Autodesk Fusion 360 part; units mm, degrees
(part 17 of 28)
  line L322 (99.1222, 11.5551) -> (98.9836, 11.4165)
  line L323 (98.9836, 11.4165) -> (98.8249, 11.3012)
  line L324 (98.8249, 11.3012) -> (98.6501, 11.2121)
  line L325 (98.6501, 11.2121) -> (98.4635, 11.1515)
  line L326 (98.4635, 11.1515) -> (98.2698, 11.1208)
  line L327 (98.2698, 11.1208) -> (98.1717, 11.117)
  line L328 (98.1717, 11.117) -> (97.6717, 11.117)
  line L329 (97.6717, 11.117) -> (97.5737, 11.1208)
  line L330 (97.5737, 11.1208) -> (97.3799, 11.1515)
  line L331 (97.3799, 11.1515) -> (97.1934, 11.2121)
  line L332 (97.1934, 11.2121) -> (97.0186, 11.3012)
  line L333 (97.0186, 11.3012) -> (96.8599, 11.4165)
  line L334 (96.8599, 11.4165) -> (96.7212, 11.5551)
  line L335 (96.7212, 11.5551) -> (96.6059, 11.7138)
  line L336 (96.6059, 11.7138) -> (96.5169, 11.8886)
  line L337 (96.5169, 11.8886) -> (96.4563, 12.0751)
  line L338 (96.4563, 12.0751) -> (96.4256, 12.2689)
  line L339 (96.4256, 12.2689) -> (96.4256, 12.465)
  line L340 (96.4256, 12.465) -> (96.4563, 12.6588)
  line L341 (96.4563, 12.6588) -> (96.5169, 12.8453)
  line L342 (96.5169, 12.8453) -> (96.6059, 13.0201)
  line L343 (96.6059, 13.0201) -> (96.7212, 13.1788)
  line L344 (96.7212, 13.1788) -> (96.8599, 13.3175)
  line L345 (96.8599, 13.3175) -> (97.0186, 13.4328)
  line L346 (97.0186, 13.4328) -> (97.1934, 13.5218)
  line L347 (97.1934, 13.5218) -> (97.3799, 13.5824)
  line L348 (97.3799, 13.5824) -> (97.5737, 13.6131)
  line L349 (97.5737, 13.6131) -> (97.6717, 13.617)
  line L350 (97.6717, 13.617) -> (98.1717, 13.617)
  line L351 (98.1717, 13.617) -> (98.2698, 13.6131)
  line L352 (43.7883, 16.6386) -> (43.9806, 16.6003)
  line L353 (43.9806, 16.6003) -> (44.1617, 16.5253)
  line L354 (44.1617, 16.5253) -> (44.3247, 16.4164)
  line L355 (44.3247, 16.4164) -> (44.4633, 16.2778)
  line L356 (44.4633, 16.2778) -> (44.5722, 16.1148)
  line L357 (44.5722, 16.1148) -> (44.6472, 15.9337)
  line L358 (44.6472, 15.9337) -> (44.6855, 15.7414)
  line L359 (44.6855, 15.7414) -> (44.6855, 15.5454)
  line L360 (44.6855, 15.5454) -> (44.6472, 15.3531)
  line L361 (44.6472, 15.3531) -> (44.5722, 15.172)
  line L362 (44.5722, 15.172) -> (44.4633, 15.009)
  line L363 (44.4633, 15.009) -> (44.3247, 14.8704)
  line L364 (44.3247, 14.8704) -> (44.1617, 14.7615)
  line L365 (44.1617, 14.7615) -> (43.9806, 14.6865)
  line L366 (43.9806, 14.6865) -> (43.7883, 14.6482)
  line L367 (43.7883, 14.6482) -> (43.6903, 14.6434)
  line L368 (43.6903, 14.6434) -> (42.4903, 14.6434)
  line L369 (42.4903, 14.6434) -> (42.3923, 14.6482)
  line L370 (42.3923, 14.6482) -> (42.2, 14.6865)
  line L371 (42.2, 14.6865) -> (42.0189, 14.7615)
  line L372 (42.0189, 14.7615) -> (41.8559, 14.8704)
  line L373 (41.8559, 14.8704) -> (41.7173, 15.009)
  line L374 (41.7173, 15.009) -> (41.6084, 15.172)
  line L375 (41.6084, 15.172) -> (41.5333, 15.3531)
  line L376 (41.5333, 15.3531) -> (41.4951, 15.5454)
  line L377 (41.4951, 15.5454) -> (41.4951, 15.7414)
  line L378 (41.4951, 15.7414) -> (41.5333, 15.9337)
  line L379 (41.5333, 15.9337) -> (41.6084, 16.1148)
  line L380 (41.6084, 16.1148) -> (41.7173, 16.2778)
  line L381 (41.7173, 16.2778) -> (41.8559, 16.4164)
  line L382 (41.8559, 16.4164) -> (42.0189, 16.5253)
  line L383 (42.0189, 16.5253) -> (42.2, 16.6003)
  line L384 (42.2, 16.6003) -> (42.3923, 16.6386)
  line L385 (42.3923, 16.6386) -> (42.4903, 16.6434)
  line L386 (42.4903, 16.6434) -> (43.6903, 16.6434)
  line L387 (43.6903, 16.6434) -> (43.7883, 16.6386)
  line L388 (104.7483, 16.6386) -> (104.9406, 16.6003)
  line L389 (104.9406, 16.6003) -> (105.1217, 16.5253)
  line L390 (105.1217, 16.5253) -> (105.2847, 16.4164)
  line L391 (105.2847, 16.4164) -> (105.4233, 16.2778)
  line L392 (105.4233, 16.2778) -> (105.5322, 16.1148)
  line L393 (105.5322, 16.1148) -> (105.6072, 15.9337)
  line L394 (105.6072, 15.9337) -> (105.6455, 15.7414)
  line L395 (105.6455, 15.7414) -> (105.6455, 15.5454)
  line L396 (105.6455, 15.5454) -> (105.6072, 15.3531)
  line L397 (105.6072, 15.3531) -> (105.5322, 15.172)
  line L398 (105.5322, 15.172) -> (105.4233, 15.009)
  line L399 (105.4233, 15.009) -> (105.2847, 14.8704)
  line L400 (105.2847, 14.8704) -> (105.1217, 14.7615)
  line L401 (105.1217, 14.7615) -> (104.9406, 14.6865)
  line L402 (104.9406, 14.6865) -> (104.7483, 14.6482)
  line L403 (104.7483, 14.6482) -> (104.6503, 14.6434)
  line L404 (104.6503, 14.6434) -> (103.4503, 14.6434)
  line L405 (103.4503, 14.6434) -> (103.3523, 14.6482)
  line L406 (103.3523, 14.6482) -> (103.16, 14.6865)
  line L407 (103.16, 14.6865) -> (102.9789, 14.7615)
  line L408 (102.9789, 14.7615) -> (102.8159, 14.8704)
  line L409 (102.8159, 14.8704) -> (102.6773, 15.009)
  line L410 (102.6773, 15.009) -> (102.5684, 15.172)
  line L411 (102.5684, 15.172) -> (102.4933, 15.3531)
  line L412 (102.4933, 15.3531) -> (102.4551, 15.5454)
  line L413 (102.4551, 15.5454) -> (102.4551, 15.7414)
  line L414 (102.4551, 15.7414) -> (102.4933, 15.9337)
  line L415 (102.4933, 15.9337) -> (102.5684, 16.1148)
  line L416 (102.5684, 16.1148) -> (102.6773, 16.2778)
  line L417 (102.6773, 16.2778) -> (102.8159, 16.4164)
  line L418 (102.8159, 16.4164) -> (102.9789, 16.5253)
  line L419 (102.9789, 16.5253) -> (103.16, 16.6003)
  line L420 (103.16, 16.6003) -> (103.3523, 16.6386)
  line L421 (103.3523, 16.6386) -> (103.4503, 16.6434)
  line L422 (103.4503, 16.6434) -> (104.6503, 16.6434)
  line L423 (104.6503, 16.6434) -> (104.7483, 16.6386)
  line L424 (21.9611, 19.0012) -> (22.151, 18.9712)
  line L425 (22.151, 18.9712) -> (22.3338, 18.9118)
  line L426 (22.3338, 18.9118) -> (22.5051, 18.8245)
  line L427 (22.5051, 18.8245) -> (22.6606, 18.7115)
  line L428 (22.6606, 18.7115) -> (22.7965, 18.5756)
  line L429 (22.7965, 18.5756) -> (22.9095, 18.4201)
  line L430 (22.9095, 18.4201) -> (22.9968, 18.2488)
  line L431 (22.9968, 18.2488) -> (23.0562, 18.066)
  line L432 (23.0562, 18.066) -> (23.0862, 17.8761)
  line L433 (23.0862, 17.8761) -> (23.0862, 17.6839)
  line L434 (23.0862, 17.6839) -> (23.0562, 17.494)
  line L435 (23.0562, 17.494) -> (22.9968, 17.3112)
  line L436 (22.9968, 17.3112) -> (22.9095, 17.1399)
  line L437 (22.9095, 17.1399) -> (22.7965, 16.9844)
  line L438 (22.7965, 16.9844) -> (22.6606, 16.8485)
  line L439 (22.6606, 16.8485) -> (22.5051, 16.7355)
  line L440 (22.5051, 16.7355) -> (22.3338, 16.6482)
  line L441 (22.3338, 16.6482) -> (22.151, 16.5888)
  line L442 (22.151, 16.5888) -> (21.9611, 16.5588)
  line L443 (21.9611, 16.5588) -> (21.865, 16.555)
  line L444 (21.865, 16.555) -> (21.315, 16.555)
  line L445 (21.315, 16.555) -> (21.2189, 16.5588)
  line L446 (21.2189, 16.5588) -> (21.029, 16.5888)
  line L447 (21.029, 16.5888) -> (20.8462, 16.6482)
  line L448 (20.8462, 16.6482) -> (20.6749, 16.7355)
  line L449 (20.6749, 16.7355) -> (20.5194, 16.8485)
  line L450 (20.5194, 16.8485) -> (20.3835, 16.9844)
  line L451 (20.3835, 16.9844) -> (20.2705, 17.1399)
  line L452 (20.2705, 17.1399) -> (20.1832, 17.3112)
  line L453 (20.1832, 17.3112) -> (20.1238, 17.494)
  line L454 (20.1238, 17.494) -> (20.0938, 17.6839)
  line L455 (20.0938, 17.6839) -> (20.0938, 17.8761)
  line L456 (20.0938, 17.8761) -> (20.1238, 18.066)
  line L457 (20.1238, 18.066) -> (20.1832, 18.2488)
  line L458 (20.1832, 18.2488) -> (20.2705, 18.4201)
  line L459 (20.2705, 18.4201) -> (20.3835, 18.5756)
  line L460 (20.3835, 18.5756) -> (20.5194, 18.7115)
  line L461 (20.5194, 18.7115) -> (20.6749, 18.8245)
  line L462 (20.6749, 18.8245) -> (20.8462, 18.9118)
  line L463 (20.8462, 18.9118) -> (21.029, 18.9712)
  line L464 (21.029, 18.9712) -> (21.2189, 19.0012)
  line L465 (21.2189, 19.0012) -> (21.315, 19.005)
  line L466 (21.315, 19.005) -> (21.865, 19.005)
  line L467 (21.865, 19.005) -> (21.9611, 19.0012)
  line L468 (82.9211, 19.0012) -> (83.111, 18.9712)
  line L469 (83.111, 18.9712) -> (83.2938, 18.9118)
  line L470 (83.2938, 18.9118) -> (83.4651, 18.8245)
  line L471 (83.4651, 18.8245) -> (83.6206, 18.7115)
  line L472 (83.6206, 18.7115) -> (83.7565, 18.5756)
  line L473 (83.7565, 18.5756) -> (83.8695, 18.4201)
  line L474 (83.8695, 18.4201) -> (83.9568, 18.2488)
  line L475 (83.9568, 18.2488) -> (84.0162, 18.066)
  line L476 (84.0162, 18.066) -> (84.0462, 17.8761)
  line L477 (84.0462, 17.8761) -> (84.0462, 17.6839)
  line L478 (84.0462, 17.6839) -> (84.0162, 17.494)
  line L479 (84.0162, 17.494) -> (83.9568, 17.3112)
  line L480 (83.9568, 17.3112) -> (83.8695, 17.1399)
  line L481 (83.8695, 17.1399) -> (83.7565, 16.9844)
  line L482 (83.7565, 16.9844) -> (83.6206, 16.8485)
  line L483 (83.6206, 16.8485) -> (83.4651, 16.7355)
  line L484 (83.4651, 16.7355) -> (83.2938, 16.6482)
  line L485 (83.2938, 16.6482) -> (83.111, 16.5888)
  line L486 (83.111, 16.5888) -> (82.9211, 16.5588)
  line L487 (82.9211, 16.5588) -> (82.825, 16.555)
  line L488 (82.825, 16.555) -> (82.275, 16.555)
  line L489 (82.275, 16.555) -> (82.1789, 16.5588)
  line L490 (82.1789, 16.5588) -> (81.989, 16.5888)
  line L491 (81.989, 16.5888) -> (81.8062, 16.6482)
  line L492 (81.8062, 16.6482) -> (81.6349, 16.7355)
  line L493 (81.6349, 16.7355) -> (81.4794, 16.8485)
  line L494 (81.4794, 16.8485) -> (81.3435, 16.9844)
  line L495 (81.3435, 16.9844) -> (81.2305, 17.1399)
  line L496 (81.2305, 17.1399) -> (81.1432, 17.3112)
  line L497 (81.1432, 17.3112) -> (81.0838, 17.494)
  line L498 (81.0838, 17.494) -> (81.0538, 17.6839)
  line L499 (81.0538, 17.6839) -> (81.0538, 17.8761)
  line L500 (81.0538, 17.8761) -> (81.0838, 18.066)
  line L501 (81.0838, 18.066) -> (81.1432, 18.2488)
  line L502 (81.1432, 18.2488) -> (81.2305, 18.4201)
  line L503 (81.2305, 18.4201) -> (81.3435, 18.5756)
  line L504 (81.3435, 18.5756) -> (81.4794, 18.7115)
  line L505 (81.4794, 18.7115) -> (81.6349, 18.8245)
  line L506 (81.6349, 18.8245) -> (81.8062, 18.9118)
  line L507 (81.8062, 18.9118) -> (81.989, 18.9712)
  line L508 (81.989, 18.9712) -> (82.1789, 19.0012)
  line L509 (82.1789, 19.0012) -> (82.275, 19.005)
  line L510 (82.275, 19.005) -> (82.825, 19.005)
  line L511 (82.825, 19.005) -> (82.9211, 19.0012)
  line L512 (43.7883, 19.3686) -> (43.9806, 19.3303)
  line L513 (43.9806, 19.3303) -> (44.1617, 19.2553)
  line L514 (44.1617, 19.2553) -> (44.3247, 19.1464)
  line L515 (44.3247, 19.1464) -> (44.4633, 19.0078)
  line L516 (44.4633, 19.0078) -> (44.5722, 18.8448)
  line L517 (44.5722, 18.8448) -> (44.6472, 18.6637)
  line L518 (44.6472, 18.6637) -> (44.6855, 18.4714)
  line L519 (44.6855, 18.4714) -> (44.6855, 18.2754)
  line L520 (44.6855, 18.2754) -> (44.6472, 18.0831)
  line L521 (44.6472, 18.0831) -> (44.5722, 17.902)
  line L522 (44.5722, 17.902) -> (44.4633, 17.739)
  line L523 (44.4633, 17.739) -> (44.3247, 17.6004)
  line L524 (44.3247, 17.6004) -> (44.1617, 17.4915)
  line L525 (44.1617, 17.4915) -> (43.9806, 17.4165)
  line L526 (43.9806, 17.4165) -> (43.7883, 17.3782)
  line L527 (43.7883, 17.3782) -> (43.6903, 17.3734)
  line L528 (43.6903, 17.3734) -> (42.4903, 17.3734)
  line L529 (42.4903, 17.3734) -> (42.3923, 17.3782)
  line L530 (42.3923, 17.3782) -> (42.2, 17.4165)
  line L531 (42.2, 17.4165) -> (42.0189, 17.4915)
  line L532 (42.0189, 17.4915) -> (41.8559, 17.6004)
  line L533 (41.8559, 17.6004) -> (41.7173, 17.739)
  line L534 (41.7173, 17.739) -> (41.6084, 17.902)
  line L535 (41.6084, 17.902) -> (41.5333, 18.0831)
  line L536 (41.5333, 18.0831) -> (41.4951, 18.2754)
  line L537 (41.4951, 18.2754) -> (41.4951, 18.4714)
  line L538 (41.4951, 18.4714) -> (41.5333, 18.6637)
  line L539 (41.5333, 18.6637) -> (41.6084, 18.8448)
  line L540 (41.6084, 18.8448) -> (41.7173, 19.0078)
  line L541 (41.7173, 19.0078) -> (41.8559, 19.1464)
  line L542 (41.8559, 19.1464) -> (42.0189, 19.2553)
  line L543 (42.0189, 19.2553) -> (42.2, 19.3303)
  line L544 (42.2, 19.3303) -> (42.3923, 19.3686)
  line L545 (42.3923, 19.3686) -> (42.4903, 19.3734)
  line L546 (42.4903, 19.3734) -> (43.6903, 19.3734)
  line L547 (43.6903, 19.3734) -> (43.7883, 19.3686)
  line L548 (104.7483, 19.3686) -> (104.9406, 19.3303)
  line L549 (104.9406, 19.3303) -> (105.1217, 19.2553)
  line L550 (105.1217, 19.2553) -> (105.2847, 19.1464)
  line L551 (105.2847, 19.1464) -> (105.4233, 19.0078)
  line L552 (105.4233, 19.0078) -> (105.5322, 18.8448)
  line L553 (105.5322, 18.8448) -> (105.6072, 18.6637)
  line L554 (105.6072, 18.6637) -> (105.6455, 18.4714)
  line L555 (105.6455, 18.4714) -> (105.6455, 18.2754)
  line L556 (105.6455, 18.2754) -> (105.6072, 18.0831)
  line L557 (105.6072, 18.0831) -> (105.5322, 17.902)
  line L558 (105.5322, 17.902) -> (105.4233, 17.739)
  line L559 (105.4233, 17.739) -> (105.2847, 17.6004)
  line L560 (105.2847, 17.6004) -> (105.1217, 17.4915)
  line L561 (105.1217, 17.4915) -> (104.9406, 17.4165)
  line L562 (104.9406, 17.4165) -> (104.7483, 17.3782)
  line L563 (104.7483, 17.3782) -> (104.6503, 17.3734)
  line L564 (104.6503, 17.3734) -> (103.4503, 17.3734)
  line L565 (103.4503, 17.3734) -> (103.3523, 17.3782)
  line L566 (103.3523, 17.3782) -> (103.16, 17.4165)
  line L567 (103.16, 17.4165) -> (102.9789, 17.4915)
  line L568 (102.9789, 17.4915) -> (102.8159, 17.6004)
  line L569 (102.8159, 17.6004) -> (102.6773, 17.739)
  line L570 (102.6773, 17.739) -> (102.5684, 17.902)
  line L571 (102.5684, 17.902) -> (102.4933, 18.0831)
  line L572 (102.4933, 18.0831) -> (102.4551, 18.2754)
  line L573 (102.4551, 18.2754) -> (102.4551, 18.4714)
  line L574 (102.4551, 18.4714) -> (102.4933, 18.6637)
  line L575 (102.4933, 18.6637) -> (102.5684, 18.8448)
  line L576 (102.5684, 18.8448) -> (102.6773, 19.0078)
  line L577 (102.6773, 19.0078) -> (102.8159, 19.1464)
  line L578 (102.8159, 19.1464) -> (102.9789, 19.2553)
  line L579 (102.9789, 19.2553) -> (103.16, 19.3303)
  line L580 (103.16, 19.3303) -> (103.3523, 19.3686)
  line L581 (103.3523, 19.3686) -> (103.4503, 19.3734)
  line L582 (103.4503, 19.3734) -> (104.6503, 19.3734)
  line L583 (104.6503, 19.3734) -> (104.7483, 19.3686)
  line L584 (22.8164, 21.4891) -> (22.9296, 21.4337)
  line L585 (22.9296, 21.4337) -> (23.0187, 21.3446)
  line L586 (23.0187, 21.3446) -> (23.0741, 21.2314)
  line L587 (23.0741, 21.2314) -> (23.09, 21.1222)
  line L588 (23.09, 21.1222) -> (23.09, 19.4378)
  line L589 (23.09, 19.4378) -> (23.0741, 19.3286)
  line L590 (23.0741, 19.3286) -> (23.0187, 19.2154)
  line L591 (23.0187, 19.2154) -> (22.9296, 19.1263)
  line L592 (22.9296, 19.1263) -> (22.8164, 19.0709)
  line L593 (22.8164, 19.0709) -> (22.7072, 19.055)
  line L594 (22.7072, 19.055) -> (20.4728, 19.055)
  line L595 (20.4728, 19.055) -> (20.3636, 19.0709)
  line L596 (20.3636, 19.0709) -> (20.2504, 19.1263)
  line L597 (20.2504, 19.1263) -> (20.1613, 19.2154)
  line L598 (20.1613, 19.2154) -> (20.1059, 19.3286)
  line L599 (20.1059, 19.3286) -> (20.09, 19.4378)
  line L600 (20.09, 19.4378) -> (20.09, 21.1222)
  line L601 (20.09, 21.1222) -> (20.1059, 21.2314)
  line L602 (20.1059, 21.2314) -> (20.1613, 21.3446)
  line L603 (20.1613, 21.3446) -> (20.2504, 21.4337)
  line L604 (20.2504, 21.4337) -> (20.3636, 21.4891)
  line L605 (20.3636, 21.4891) -> (20.4728, 21.505)
  line L606 (20.4728, 21.505) -> (22.7072, 21.505)
  line L607 (22.7072, 21.505) -> (22.8164, 21.4891)
  line L608 (83.7764, 21.4891) -> (83.8896, 21.4337)
  line L609 (83.8896, 21.4337) -> (83.9787, 21.3446)
  line L610 (83.9787, 21.3446) -> (84.0341, 21.2314)
  line L611 (84.0341, 21.2314) -> (84.05, 21.1222)
  line L612 (84.05, 21.1222) -> (84.05, 19.4378)
  line L613 (84.05, 19.4378) -> (84.0341, 19.3286)
  line L614 (84.0341, 19.3286) -> (83.9787, 19.2154)
  line L615 (83.9787, 19.2154) -> (83.8896, 19.1263)
  line L616 (83.8896, 19.1263) -> (83.7764, 19.0709)
  line L617 (83.7764, 19.0709) -> (83.6672, 19.055)
  line L618 (83.6672, 19.055) -> (81.4328, 19.055)
  line L619 (81.4328, 19.055) -> (81.3236, 19.0709)
  line L620 (81.3236, 19.0709) -> (81.2104, 19.1263)
  line L621 (81.2104, 19.1263) -> (81.1213, 19.2154)
  line L622 (81.1213, 19.2154) -> (81.0659, 19.3286)
  line L623 (81.0659, 19.3286) -> (81.05, 19.4378)
  line L624 (81.05, 19.4378) -> (81.05, 21.1222)
  line L625 (81.05, 21.1222) -> (81.0659, 21.2314)
  line L626 (81.0659, 21.2314) -> (81.1213, 21.3446)
  line L627 (81.1213, 21.3446) -> (81.2104, 21.4337)
  line L628 (81.2104, 21.4337) -> (81.3236, 21.4891)
  line L629 (81.3236, 21.4891) -> (81.4328, 21.505)
  line L630 (81.4328, 21.505) -> (83.6672, 21.505)
  line L631 (83.6672, 21.505) -> (83.7764, 21.4891)
  line L632 (32.7136, 22.7426) -> (32.9001, 22.682)
  line L633 (32.9001, 22.682) -> (33.0749, 22.5929)
  line L634 (33.0749, 22.5929) -> (33.2336, 22.4776)
  line L635 (33.2336, 22.4776) -> (33.3723, 22.3389)
  line L636 (33.3723, 22.3389) -> (33.4876, 22.1802)
  line L637 (33.4876, 22.1802) -> (33.5766, 22.0055)
  line L638 (33.5766, 22.0055) -> (33.6372, 21.8189)
  line L639 (33.6372, 21.8189) -> (33.6679, 21.6252)
  line L640 (33.6679, 21.6252) -> (33.6718, 21.5271)
  line L641 (33.6718, 21.5271) -> (33.6718, 21.0271)
  line L642 (33.6718, 21.0271) -> (33.6679, 20.929)
  line L643 (33.6679, 20.929) -> (33.6372, 20.7353)
  line L644 (33.6372, 20.7353) -> (33.5766, 20.5488)
  line L645 (33.5766, 20.5488) -> (33.4876, 20.374)
  line L646 (33.4876, 20.374) -> (33.3723, 20.2153)
  line L647 (33.3723, 20.2153) -> (33.2336, 20.0766)
  line L648 (33.2336, 20.0766) -> (33.0749, 19.9613)
  line L649 (33.0749, 19.9613) -> (32.9001, 19.8723)
  line L650 (32.9001, 19.8723) -> (32.7136, 19.8117)
  line L651 (32.7136, 19.8117) -> (32.5198, 19.781)
  line L652 (32.5198, 19.781) -> (32.3237, 19.781)
  line L653 (32.3237, 19.781) -> (32.13, 19.8117)
  line L654 (32.13, 19.8117) -> (31.9434, 19.8723)
  line L655 (31.9434, 19.8723) -> (31.7686, 19.9613)
  line L656 (31.7686, 19.9613) -> (31.61, 20.0766)
  line L657 (31.61, 20.0766) -> (31.4713, 20.2153)
  line L658 (31.4713, 20.2153) -> (31.356, 20.374)
  line L659 (31.356, 20.374) -> (31.2669, 20.5488)
  line L660 (31.2669, 20.5488) -> (31.2063, 20.7353)
  line L661 (31.2063, 20.7353) -> (31.1756, 20.929)
  line L662 (31.1756, 20.929) -> (31.1718, 21.0271)
  line L663 (31.1718, 21.0271) -> (31.1718, 21.5271)
  line L664 (31.1718, 21.5271) -> (31.1756, 21.6252)
  line L665 (31.1756, 21.6252) -> (31.2063, 21.8189)
  line L666 (31.2063, 21.8189) -> (31.2669, 22.0055)
  line L667 (31.2669, 22.0055) -> (31.356, 22.1802)
  line L668 (31.356, 22.1802) -> (31.4713, 22.3389)
  line L669 (31.4713, 22.3389) -> (31.61, 22.4776)
  line L670 (31.61, 22.4776) -> (31.7686, 22.5929)
  line L671 (31.7686, 22.5929) -> (31.9434, 22.682)
  line L672 (31.9434, 22.682) -> (32.13, 22.7426)
  line L673 (32.13, 22.7426) -> (32.3237, 22.7733)
  line L674 (32.3237, 22.7733) -> (32.5198, 22.7733)
  line L675 (32.5198, 22.7733) -> (32.7136, 22.7426)
  line L676 (93.6736, 22.7426) -> (93.8601, 22.682)
  line L677 (93.8601, 22.682) -> (94.0349, 22.5929)
  line L678 (94.0349, 22.5929) -> (94.1936, 22.4776)
  line L679 (94.1936, 22.4776) -> (94.3323, 22.3389)
  line L680 (94.3323, 22.3389) -> (94.4476, 22.1802)
  line L681 (94.4476, 22.1802) -> (94.5366, 22.0055)
  line L682 (94.5366, 22.0055) -> (94.5972, 21.8189)
  line L683 (94.5972, 21.8189) -> (94.6279, 21.6252)
  line L684 (94.6279, 21.6252) -> (94.6318, 21.5271)
  line L685 (94.6318, 21.5271) -> (94.6318, 21.0271)
  line L686 (94.6318, 21.0271) -> (94.6279, 20.929)
  line L687 (94.6279, 20.929) -> (94.5972, 20.7353)
  line L688 (94.5972, 20.7353) -> (94.5366, 20.5488)
  line L689 (94.5366, 20.5488) -> (94.4476, 20.374)
  line L690 (94.4476, 20.374) -> (94.3323, 20.2153)
  line L691 (94.3323, 20.2153) -> (94.1936, 20.0766)
  line L692 (94.1936, 20.0766) -> (94.0349, 19.9613)
  line L693 (94.0349, 19.9613) -> (93.8601, 19.8723)
  line L694 (93.8601, 19.8723) -> (93.6736, 19.8117)
  line L695 (93.6736, 19.8117) -> (93.4798, 19.781)
  line L696 (93.4798, 19.781) -> (93.2837, 19.781)
  line L697 (93.2837, 19.781) -> (93.09, 19.8117)
  line L698 (93.09, 19.8117) -> (92.9034, 19.8723)
  line L699 (92.9034, 19.8723) -> (92.7286, 19.9613)
  line L700 (92.7286, 19.9613) -> (92.57, 20.0766)
  line L701 (92.57, 20.0766) -> (92.4313, 20.2153)
  line L702 (92.4313, 20.2153) -> (92.316, 20.374)
  line L703 (92.316, 20.374) -> (92.2269, 20.5488)
  line L704 (92.2269, 20.5488) -> (92.1663, 20.7353)
  line L705 (92.1663, 20.7353) -> (92.1356, 20.929)
  line L706 (92.1356, 20.929) -> (92.1318, 21.0271)
  line L707 (92.1318, 21.0271) -> (92.1318, 21.5271)
  line L708 (92.1318, 21.5271) -> (92.1356, 21.6252)
  line L709 (92.1356, 21.6252) -> (92.1663, 21.8189)
  line L710 (92.1663, 21.8189) -> (92.2269, 22.0055)
  line L711 (92.2269, 22.0055) -> (92.316, 22.1802)
  line L712 (92.316, 22.1802) -> (92.4313, 22.3389)
  line L713 (92.4313, 22.3389) -> (92.57, 22.4776)
  line L714 (92.57, 22.4776) -> (92.7286, 22.5929)
  line L715 (92.7286, 22.5929) -> (92.9034, 22.682)
  line L716 (92.9034, 22.682) -> (93.09, 22.7426)
  line L717 (93.09, 22.7426) -> (93.2837, 22.7733)
  line L718 (93.2837, 22.7733) -> (93.4798, 22.7733)
  line L719 (93.4798, 22.7733) -> (93.6736, 22.7426)
  line L720 (44.6903, 20.1434) -> (41.4903, 20.1434)
  line L721 (41.4903, 20.1434) -> (41.4903, 22.1434)
  line L722 (41.4903, 22.1434) -> (44.6903, 22.1434)
  line L723 (44.6903, 22.1434) -> (44.6903, 20.1434)
  line L724 (105.6503, 20.1434) -> (102.4503, 20.1434)
  line L725 (102.4503, 20.1434) -> (102.4503, 22.1434)
  line L726 (102.4503, 22.1434) -> (105.6503, 22.1434)
  line L727 (105.6503, 22.1434) -> (105.6503, 20.1434)
  line L728 (60.3233, 20.3326) -> (57.3233, 20.3326)
  line L729 (57.3233, 20.3326) -> (57.3233, 22.7826)
  line L730 (57.3233, 22.7826) -> (60.3233, 22.7826)
  line L731 (60.3233, 22.7826) -> (60.3233, 20.3326)
  line L732 (121.2833, 20.3326) -> (118.2833, 20.3326)
  line L733 (118.2833, 20.3326) -> (118.2833, 22.7826)
  line L734 (118.2833, 22.7826) -> (121.2833, 22.7826)
  line L735 (121.2833, 22.7826) -> (121.2833, 20.3326)
  line L736 (50.1338, 24.7863) -> (50.3204, 24.7257)
  line L737 (50.3204, 24.7257) -> (50.4952, 24.6366)
  line L738 (50.4952, 24.6366) -> (50.6538, 24.5213)
  line L739 (50.6538, 24.5213) -> (50.7925, 24.3826)
  line L740 (50.7925, 24.3826) -> (50.9078, 24.2239)
  line L741 (50.9078, 24.2239) -> (50.9969, 24.0492)
  line L742 (50.9969, 24.0492) -> (51.0575, 23.8626)
  line L743 (51.0575, 23.8626) -> (51.0882, 23.6689)
  line L744 (51.0882, 23.6689) -> (51.092, 23.5708)
  line L745 (51.092, 23.5708) -> (51.092, 23.0708)
  line L746 (51.092, 23.0708) -> (51.0882, 22.9727)
  line L747 (51.0882, 22.9727) -> (51.0575, 22.779)
  line L748 (51.0575, 22.779) -> (50.9969, 22.5925)
  line L749 (50.9969, 22.5925) -> (50.9078, 22.4177)
  line L750 (50.9078, 22.4177) -> (50.7925, 22.259)
  line L751 (50.7925, 22.259) -> (50.6538, 22.1203)
  line L752 (50.6538, 22.1203) -> (50.4952, 22.005)
  line L753 (50.4952, 22.005) -> (50.3204, 21.916)
  line L754 (50.3204, 21.916) -> (50.1338, 21.8554)
  line L755 (50.1338, 21.8554) -> (49.9401, 21.8247)
  line L756 (49.9401, 21.8247) -> (49.744, 21.8247)
  line L757 (49.744, 21.8247) -> (49.5502, 21.8554)
  line L758 (49.5502, 21.8554) -> (49.3637, 21.916)
  line L759 (49.3637, 21.916) -> (49.1889, 22.005)
  line L760 (49.1889, 22.005) -> (49.0302, 22.1203)
  line L761 (49.0302, 22.1203) -> (48.8915, 22.259)
  line L762 (48.8915, 22.259) -> (48.7762, 22.4177)
  line L763 (48.7762, 22.4177) -> (48.6872, 22.5925)
  line L764 (48.6872, 22.5925) -> (48.6266, 22.779)
  line L765 (48.6266, 22.779) -> (48.5959, 22.9727)
  line L766 (48.5959, 22.9727) -> (48.592, 23.0708)
  line L767 (48.592, 23.0708) -> (48.592, 23.5708)
  line L768 (48.592, 23.5708) -> (48.5959, 23.6689)
  line L769 (48.5959, 23.6689) -> (48.6266, 23.8626)
  line L770 (48.6266, 23.8626) -> (48.6872, 24.0492)
  line L771 (48.6872, 24.0492) -> (48.7762, 24.2239)
  line L772 (48.7762, 24.2239) -> (48.8915, 24.3826)
  line L773 (48.8915, 24.3826) -> (49.0302, 24.5213)
  line L774 (49.0302, 24.5213) -> (49.1889, 24.6366)
  line L775 (49.1889, 24.6366) -> (49.3637, 24.7257)
  line L776 (49.3637, 24.7257) -> (49.5502, 24.7863)
  line L777 (49.5502, 24.7863) -> (49.744, 24.817)
  line L778 (49.744, 24.817) -> (49.9401, 24.817)
  line L779 (49.9401, 24.817) -> (50.1338, 24.7863)
  line L780 (111.0938, 24.7863) -> (111.2804, 24.7257)
  line L781 (111.2804, 24.7257) -> (111.4552, 24.6366)
  line L782 (111.4552, 24.6366) -> (111.6138, 24.5213)
  line L783 (111.6138, 24.5213) -> (111.7525, 24.3826)
  line L784 (111.7525, 24.3826) -> (111.8678, 24.2239)
  line L785 (111.8678, 24.2239) -> (111.9569, 24.0492)
  line L786 (111.9569, 24.0492) -> (112.0175, 23.8626)
  line L787 (112.0175, 23.8626) -> (112.0482, 23.6689)
  line L788 (112.0482, 23.6689) -> (112.052, 23.5708)
  line L789 (112.052, 23.5708) -> (112.052, 23.0708)
  line L790 (112.052, 23.0708) -> (112.0482, 22.9727)
  line L791 (112.0482, 22.9727) -> (112.0175, 22.779)
  line L792 (112.0175, 22.779) -> (111.9569, 22.5925)
  line L793 (111.9569, 22.5925) -> (111.8678, 22.4177)
  line L794 (111.8678, 22.4177) -> (111.7525, 22.259)
  line L795 (111.7525, 22.259) -> (111.6138, 22.1203)
  line L796 (111.6138, 22.1203) -> (111.4552, 22.005)
  line L797 (111.4552, 22.005) -> (111.2804, 21.916)
  line L798 (111.2804, 21.916) -> (111.0938, 21.8554)
  line L799 (111.0938, 21.8554) -> (110.9001, 21.8247)
  line L800 (110.9001, 21.8247) -> (110.704, 21.8247)
  line L801 (110.704, 21.8247) -> (110.5102, 21.8554)
  line L802 (110.5102, 21.8554) -> (110.3237, 21.916)
  line L803 (110.3237, 21.916) -> (110.1489, 22.005)
  line L804 (110.1489, 22.005) -> (109.9902, 22.1203)
  line L805 (109.9902, 22.1203) -> (109.8515, 22.259)
  line L806 (109.8515, 22.259) -> (109.7362, 22.4177)
  line L807 (109.7362, 22.4177) -> (109.6472, 22.5925)
  line L808 (109.6472, 22.5925) -> (109.5866, 22.779)
  line L809 (109.5866, 22.779) -> (109.5559, 22.9727)
  line L810 (109.5559, 22.9727) -> (109.552, 23.0708)
  line L811 (109.552, 23.0708) -> (109.552, 23.5708)
  line L812 (109.552, 23.5708) -> (109.5559, 23.6689)
  line L813 (109.5559, 23.6689) -> (109.5866, 23.8626)
  line L814 (109.5866, 23.8626) -> (109.6472, 24.0492)
  line L815 (109.6472, 24.0492) -> (109.7362, 24.2239)
  line L816 (109.7362, 24.2239) -> (109.8515, 24.3826)
  line L817 (109.8515, 24.3826) -> (109.9902, 24.5213)
  line L818 (109.9902, 24.5213) -> (110.1489, 24.6366)
  line L819 (110.1489, 24.6366) -> (110.3237, 24.7257)
  line L820 (110.3237, 24.7257) -> (110.5102, 24.7863)
  line L821 (110.5102, 24.7863) -> (110.704, 24.817)
  line L822 (110.704, 24.817) -> (110.9001, 24.817)
  line L823 (110.9001, 24.817) -> (111.0938, 24.7863)
  line L824 (59.0529, 25.551) -> (59.1886, 25.4727)
  line L825 (59.1886, 25.4727) -> (59.2993, 25.3619)
  line L826 (59.2993, 25.3619) -> (59.3373, 25.2962)
  line L827 (59.3373, 25.2962) -> (59.3843, 25.2888)
  line L828 (59.3843, 25.2888) -> (59.5671, 25.2294)
  line L829 (59.5671, 25.2294) -> (59.7384, 25.1421)
  line L830 (59.7384, 25.1421) -> (59.8939, 25.0291)
  line L831 (59.8939, 25.0291) -> (60.0298, 24.8932)
  line L832 (60.0298, 24.8932) -> (60.1428, 24.7377)
  line L833 (60.1428, 24.7377) -> (60.2301, 24.5664)
  line L834 (60.2301, 24.5664) -> (60.2895, 24.3836)
  line L835 (60.2895, 24.3836) -> (60.3195, 24.1937)
  line L836 (60.3195, 24.1937) -> (60.3195, 24.0015)
  line L837 (60.3195, 24.0015) -> (60.2895, 23.8117)
  line L838 (60.2895, 23.8117) -> (60.2301, 23.6288)
  line L839 (60.2301, 23.6288) -> (60.1428, 23.4576)
  line L840 (60.1428, 23.4576) -> (60.0298, 23.3021)
  line L841 (60.0298, 23.3021) -> (59.8939, 23.1661)
  line L842 (59.8939, 23.1661) -> (59.7384, 23.0531)
  line L843 (59.7384, 23.0531) -> (59.5671, 22.9659)
  line L844 (59.5671, 22.9659) -> (59.3843, 22.9065)
  line L845 (59.3843, 22.9065) -> (59.1944, 22.8764)
  line L846 (59.1944, 22.8764) -> (59.0983, 22.8726)
  line L847 (59.0983, 22.8726) -> (58.5483, 22.8726)
  line L848 (58.5483, 22.8726) -> (58.4522, 22.8764)
  line L849 (58.4522, 22.8764) -> (58.2623, 22.9065)
  line L850 (58.2623, 22.9065) -> (58.0795, 22.9659)
  line L851 (58.0795, 22.9659) -> (57.9083, 23.0531)
  line L852 (57.9083, 23.0531) -> (57.7527, 23.1661)
  line L853 (57.7527, 23.1661) -> (57.6168, 23.3021)
  line L854 (57.6168, 23.3021) -> (57.5038, 23.4576)
  line L855 (57.5038, 23.4576) -> (57.4166, 23.6288)
  line L856 (57.4166, 23.6288) -> (57.3572, 23.8117)
  line L857 (57.3572, 23.8117) -> (57.3271, 24.0015)
  line L858 (57.3271, 24.0015) -> (57.3271, 24.1937)
  line L859 (57.3271, 24.1937) -> (57.3572, 24.3836)
  line L860 (57.3572, 24.3836) -> (57.4166, 24.5664)
  line L861 (57.4166, 24.5664) -> (57.5038, 24.7377)
  line L862 (57.5038, 24.7377) -> (57.6168, 24.8932)
  line L863 (57.6168, 24.8932) -> (57.7527, 25.0291)
  line L864 (57.7527, 25.0291) -> (57.9083, 25.1421)
  line L865 (57.9083, 25.1421) -> (58.0795, 25.2294)
  line L866 (58.0795, 25.2294) -> (58.2623, 25.2888)
  line L867 (58.2623, 25.2888) -> (58.3094, 25.2962)
  line L868 (58.3094, 25.2962) -> (58.3473, 25.3619)
  line L869 (58.3473, 25.3619) -> (58.4581, 25.4727)
  line L870 (58.4581, 25.4727) -> (58.5937, 25.551)
  line L871 (58.5937, 25.551) -> (58.745, 25.5916)
  line L872 (58.745, 25.5916) -> (58.9016, 25.5916)
  line L873 (58.9016, 25.5916) -> (59.0529, 25.551)
  line L874 (120.0129, 25.551) -> (120.1486, 25.4727)
  line L875 (120.1486, 25.4727) -> (120.2593, 25.3619)
  line L876 (120.2593, 25.3619) -> (120.2973, 25.2962)
  line L877 (120.2973, 25.2962) -> (120.3443, 25.2888)
  line L878 (120.3443, 25.2888) -> (120.5271, 25.2294)
  line L879 (120.5271, 25.2294) -> (120.6984, 25.1421)
  line L880 (120.6984, 25.1421) -> (120.8539, 25.0291)
  line L881 (120.8539, 25.0291) -> (120.9898, 24.8932)
  line L882 (120.9898, 24.8932) -> (121.1028, 24.7377)
  line L883 (121.1028, 24.7377) -> (121.1901, 24.5664)
  line L884 (121.1901, 24.5664) -> (121.2495, 24.3836)
  line L885 (121.2495, 24.3836) -> (121.2795, 24.1937)
  line L886 (121.2795, 24.1937) -> (121.2795, 24.0015)
  line L887 (121.2795, 24.0015) -> (121.2495, 23.8117)
  line L888 (121.2495, 23.8117) -> (121.1901, 23.6288)
  line L889 (121.1901, 23.6288) -> (121.1028, 23.4576)
  line L890 (121.1028, 23.4576) -> (120.9898, 23.3021)
  line L891 (120.9898, 23.3021) -> (120.8539, 23.1661)
  line L892 (120.8539, 23.1661) -> (120.6984, 23.0531)
  line L893 (120.6984, 23.0531) -> (120.5271, 22.9659)
  line L894 (120.5271, 22.9659) -> (120.3443, 22.9065)
  line L895 (120.3443, 22.9065) -> (120.1544, 22.8764)
  line L896 (120.1544, 22.8764) -> (120.0583, 22.8726)
  line L897 (120.0583, 22.8726) -> (119.5083, 22.8726)
  line L898 (119.5083, 22.8726) -> (119.4122, 22.8764)
  line L899 (119.4122, 22.8764) -> (119.2223, 22.9065)
  line L900 (119.2223, 22.9065) -> (119.0395, 22.9659)
  line L901 (119.0395, 22.9659) -> (118.8683, 23.0531)
  line L902 (118.8683, 23.0531) -> (118.7127, 23.1661)
  line L903 (118.7127, 23.1661) -> (118.5768, 23.3021)
  line L904 (118.5768, 23.3021) -> (118.4638, 23.4576)
  line L905 (118.4638, 23.4576) -> (118.3766, 23.6288)
  line L906 (118.3766, 23.6288) -> (118.3172, 23.8117)
  line L907 (118.3172, 23.8117) -> (118.2871, 24.0015)
  line L908 (118.2871, 24.0015) -> (118.2871, 24.1937)
  line L909 (118.2871, 24.1937) -> (118.3172, 24.3836)
  line L910 (118.3172, 24.3836) -> (118.3766, 24.5664)
  line L911 (118.3766, 24.5664) -> (118.4638, 24.7377)
  line L912 (118.4638, 24.7377) -> (118.5768, 24.8932)
  line L913 (118.5768, 24.8932) -> (118.7127, 25.0291)
  line L914 (118.7127, 25.0291) -> (118.8683, 25.1421)
  line L915 (118.8683, 25.1421) -> (119.0395, 25.2294)
  line L916 (119.0395, 25.2294) -> (119.2223, 25.2888)
  line L917 (119.2223, 25.2888) -> (119.2694, 25.2962)
  line L918 (119.2694, 25.2962) -> (119.3073, 25.3619)
  line L919 (119.3073, 25.3619) -> (119.4181, 25.4727)
  line L920 (119.4181, 25.4727) -> (119.5537, 25.551)
  line L921 (119.5537, 25.551) -> (119.705, 25.5916)
  line L922 (119.705, 25.5916) -> (119.8616, 25.5916)
  line L923 (119.8616, 25.5916) -> (120.0129, 25.551)
  line L924 (43.8465, 27.1737) -> (44.0388, 27.1354)
  line L925 (44.0388, 27.1354) -> (44.2199, 27.0604)
  line L926 (44.2199, 27.0604) -> (44.3829, 26.9515)
  line L927 (44.3829, 26.9515) -> (44.5215, 26.8129)
  line L928 (44.5215, 26.8129) -> (44.6304, 26.6499)
  line L929 (44.6304, 26.6499) -> (44.7054, 26.4688)
  line L930 (44.7054, 26.4688) -> (44.7437, 26.2765)
  line L931 (44.7437, 26.2765) -> (44.7437, 26.0805)
  line L932 (44.7437, 26.0805) -> (44.7054, 25.8882)
  line L933 (44.7054, 25.8882) -> (44.6304, 25.7071)
  line L934 (44.6304, 25.7071) -> (44.5215, 25.5441)
  line L935 (44.5215, 25.5441) -> (44.3829, 25.4055)
  line L936 (44.3829, 25.4055) -> (44.2199, 25.2966)
  line L937 (44.2199, 25.2966) -> (44.0388, 25.2215)
  line L938 (44.0388, 25.2215) -> (43.8465, 25.1833)
  line L939 (43.8465, 25.1833) -> (43.7485, 25.1785)
  line L940 (43.7485, 25.1785) -> (42.5485, 25.1785)
  line L941 (42.5485, 25.1785) -> (42.4505, 25.1833)
  line L942 (42.4505, 25.1833) -> (42.2582, 25.2215)
  line L943 (42.2582, 25.2215) -> (42.0771, 25.2966)
  line L944 (42.0771, 25.2966) -> (41.9141, 25.4055)
  line L945 (41.9141, 25.4055) -> (41.7755, 25.5441)
  line L946 (41.7755, 25.5441) -> (41.6666, 25.7071)
  line L947 (41.6666, 25.7071) -> (41.5915, 25.8882)
  line L948 (41.5915, 25.8882) -> (41.5533, 26.0805)
  line L949 (41.5533, 26.0805) -> (41.5533, 26.2765)
  line L950 (41.5533, 26.2765) -> (41.5915, 26.4688)
  line L951 (41.5915, 26.4688) -> (41.6666, 26.6499)
  line L952 (41.6666, 26.6499) -> (41.7755, 26.8129)
  line L953 (41.7755, 26.8129) -> (41.9141, 26.9515)
  line L954 (41.9141, 26.9515) -> (42.0771, 27.0604)
  line L955 (42.0771, 27.0604) -> (42.2582, 27.1354)
  line L956 (42.2582, 27.1354) -> (42.4505, 27.1737)
  line L957 (42.4505, 27.1737) -> (42.5485, 27.1785)
  line L958 (42.5485, 27.1785) -> (43.7485, 27.1785)
  line L959 (43.7485, 27.1785) -> (43.8465, 27.1737)
  line L960 (104.8065, 27.1737) -> (104.9988, 27.1354)
  line L961 (104.9988, 27.1354) -> (105.1799, 27.0604)
  line L962 (105.1799, 27.0604) -> (105.3429, 26.9515)
  line L963 (105.3429, 26.9515) -> (105.4815, 26.8129)
  line L964 (105.4815, 26.8129) -> (105.5904, 26.6499)
  line L965 (105.5904, 26.6499) -> (105.6654, 26.4688)
  line L966 (105.6654, 26.4688) -> (105.7037, 26.2765)
  line L967 (105.7037, 26.2765) -> (105.7037, 26.0805)
  line L968 (105.7037, 26.0805) -> (105.6654, 25.8882)
  line L969 (105.6654, 25.8882) -> (105.5904, 25.7071)
  line L970 (105.5904, 25.7071) -> (105.4815, 25.5441)
  line L971 (105.4815, 25.5441) -> (105.3429, 25.4055)
  line L972 (105.3429, 25.4055) -> (105.1799, 25.2966)
  line L973 (105.1799, 25.2966) -> (104.9988, 25.2215)
  line L974 (104.9988, 25.2215) -> (104.8065, 25.1833)
  line L975 (104.8065, 25.1833) -> (104.7085, 25.1785)
  line L976 (104.7085, 25.1785) -> (103.5085, 25.1785)
  line L977 (103.5085, 25.1785) -> (103.4105, 25.1833)
  line L978 (103.4105, 25.1833) -> (103.2182, 25.2215)
  line L979 (103.2182, 25.2215) -> (103.0371, 25.2966)
  line L980 (103.0371, 25.2966) -> (102.8741, 25.4055)
  line L981 (102.8741, 25.4055) -> (102.7355, 25.5441)
  line L982 (102.7355, 25.5441) -> (102.6266, 25.7071)
  line L983 (102.6266, 25.7071) -> (102.5515, 25.8882)
  line L984 (102.5515, 25.8882) -> (102.5133, 26.0805)
  line L985 (102.5133, 26.0805) -> (102.5133, 26.2765)
  line L986 (102.5133, 26.2765) -> (102.5515, 26.4688)
  line L987 (102.5515, 26.4688) -> (102.6266, 26.6499)
  line L988 (102.6266, 26.6499) -> (102.7355, 26.8129)
  line L989 (102.7355, 26.8129) -> (102.8741, 26.9515)
  line L990 (102.8741, 26.9515) -> (103.0371, 27.0604)
  line L991 (103.0371, 27.0604) -> (103.2182, 27.1354)
  line L992 (103.2182, 27.1354) -> (103.4105, 27.1737)
  line L993 (103.4105, 27.1737) -> (103.5085, 27.1785)
  line L994 (103.5085, 27.1785) -> (104.7085, 27.1785)
  line L995 (104.7085, 27.1785) -> (104.8065, 27.1737)
  line L996 (32.7136, 30.3626) -> (32.9001, 30.302)
  line L997 (32.9001, 30.302) -> (33.0749, 30.2129)
  line L998 (33.0749, 30.2129) -> (33.2336, 30.0976)
  line L999 (33.2336, 30.0976) -> (33.3723, 29.9589)
  line L1000 (33.3723, 29.9589) -> (33.4876, 29.8002)
  line L1001 (33.4876, 29.8002) -> (33.5766, 29.6255)
  line L1002 (33.5766, 29.6255) -> (33.6372, 29.4389)
  line L1003 (33.6372, 29.4389) -> (33.6679, 29.2452)
  line L1004 (33.6679, 29.2452) -> (33.6718, 29.1471)
  line L1005 (33.6718, 29.1471) -> (33.6718, 28.6471)
  line L1006 (33.6718, 28.6471) -> (33.6679, 28.549)
  line L1007 (33.6679, 28.549) -> (33.6372, 28.3553)
  line L1008 (33.6372, 28.3553) -> (33.5766, 28.1688)
  line L1009 (33.5766, 28.1688) -> (33.4876, 27.994)
  line L1010 (33.4876, 27.994) -> (33.3723, 27.8353)
  line L1011 (33.3723, 27.8353) -> (33.2336, 27.6966)
  line L1012 (33.2336, 27.6966) -> (33.0749, 27.5813)
  line L1013 (33.0749, 27.5813) -> (32.9001, 27.4923)
  line L1014 (32.9001, 27.4923) -> (32.7136, 27.4317)
  line L1015 (32.7136, 27.4317) -> (32.5198, 27.401)
  line L1016 (32.5198, 27.401) -> (32.3237, 27.401)
  line L1017 (32.3237, 27.401) -> (32.13, 27.4317)
  line L1018 (32.13, 27.4317) -> (31.9434, 27.4923)
  line L1019 (31.9434, 27.4923) -> (31.7686, 27.5813)
  line L1020 (31.7686, 27.5813) -> (31.61, 27.6966)
  line L1021 (31.61, 27.6966) -> (31.4713, 27.8353)
  line L1022 (31.4713, 27.8353) -> (31.356, 27.994)
  line L1023 (31.356, 27.994) -> (31.2669, 28.1688)
  line L1024 (31.2669, 28.1688) -> (31.2063, 28.3553)
  line L1025 (31.2063, 28.3553) -> (31.1756, 28.549)
  line L1026 (31.1756, 28.549) -> (31.1718, 28.6471)
  line L1027 (31.1718, 28.6471) -> (31.1718, 29.1471)
  line L1028 (31.1718, 29.1471) -> (31.1756, 29.2452)
  line L1029 (31.1756, 29.2452) -> (31.2063, 29.4389)
  line L1030 (31.2063, 29.4389) -> (31.2669, 29.6255)
  line L1031 (31.2669, 29.6255) -> (31.356, 29.8002)
  line L1032 (31.356, 29.8002) -> (31.4713, 29.9589)
  line L1033 (31.4713, 29.9589) -> (31.61, 30.0976)
  line L1034 (31.61, 30.0976) -> (31.7686, 30.2129)
  line L1035 (31.7686, 30.2129) -> (31.9434, 30.302)
  line L1036 (31.9434, 30.302) -> (32.13, 30.3626)
  line L1037 (32.13, 30.3626) -> (32.3237, 30.3933)
  line L1038 (32.3237, 30.3933) -> (32.5198, 30.3933)
  line L1039 (32.5198, 30.3933) -> (32.7136, 30.3626)
  line L1040 (93.6736, 30.3626) -> (93.8601, 30.302)
  line L1041 (93.8601, 30.302) -> (94.0349, 30.2129)
  line L1042 (94.0349, 30.2129) -> (94.1936, 30.0976)
  line L1043 (94.1936, 30.0976) -> (94.3323, 29.9589)
  line L1044 (94.3323, 29.9589) -> (94.4476, 29.8002)
  line L1045 (94.4476, 29.8002) -> (94.5366, 29.6255)
  line L1046 (94.5366, 29.6255) -> (94.5972, 29.4389)
  line L1047 (94.5972, 29.4389) -> (94.6279, 29.2452)
  line L1048 (94.6279, 29.2452) -> (94.6318, 29.1471)
  line L1049 (94.6318, 29.1471) -> (94.6318, 28.6471)
  line L1050 (94.6318, 28.6471) -> (94.6279, 28.549)
  line L1051 (94.6279, 28.549) -> (94.5972, 28.3553)
  line L1052 (94.5972, 28.3553) -> (94.5366, 28.1688)
  line L1053 (94.5366, 28.1688) -> (94.4476, 27.994)
  line L1054 (94.4476, 27.994) -> (94.3323, 27.8353)
  line L1055 (94.3323, 27.8353) -> (94.1936, 27.6966)
  line L1056 (94.1936, 27.6966) -> (94.0349, 27.5813)
  line L1057 (94.0349, 27.5813) -> (93.8601, 27.4923)
  line L1058 (93.8601, 27.4923) -> (93.6736, 27.4317)
  line L1059 (93.6736, 27.4317) -> (93.4798, 27.401)
  line L1060 (93.4798, 27.401) -> (93.2837, 27.401)
  line L1061 (93.2837, 27.401) -> (93.09, 27.4317)
  line L1062 (93.09, 27.4317) -> (92.9034, 27.4923)
  line L1063 (92.9034, 27.4923) -> (92.7286, 27.5813)
  line L1064 (92.7286, 27.5813) -> (92.57, 27.6966)
  line L1065 (92.57, 27.6966) -> (92.4313, 27.8353)
  line L1066 (92.4313, 27.8353) -> (92.316, 27.994)
  line L1067 (92.316, 27.994) -> (92.2269, 28.1688)
  line L1068 (92.2269, 28.1688) -> (92.1663, 28.3553)
  line L1069 (92.1663, 28.3553) -> (92.1356, 28.549)
  line L1070 (92.1356, 28.549) -> (92.1318, 28.6471)
  line L1071 (92.1318, 28.6471) -> (92.1318, 29.1471)
  line L1072 (92.1318, 29.1471) -> (92.1356, 29.2452)
  line L1073 (92.1356, 29.2452) -> (92.1663, 29.4389)
  line L1074 (92.1663, 29.4389) -> (92.2269, 29.6255)
  line L1075 (92.2269, 29.6255) -> (92.316, 29.8002)
  line L1076 (92.316, 29.8002) -> (92.4313, 29.9589)
  line L1077 (92.4313, 29.9589) -> (92.57, 30.0976)
  line L1078 (92.57, 30.0976) -> (92.7286, 30.2129)
  line L1079 (92.7286, 30.2129) -> (92.9034, 30.302)
  line L1080 (92.9034, 30.302) -> (93.09, 30.3626)
  line L1081 (93.09, 30.3626) -> (93.2837, 30.3933)
  line L1082 (93.2837, 30.3933) -> (93.4798, 30.3933)
  line L1083 (93.4798, 30.3933) -> (93.6736, 30.3626)
  line L1084 (22.3742, 30.1765) -> (22.5641, 30.1465)
  line L1085 (22.5641, 30.1465) -> (22.7469, 30.0871)
  line L1086 (22.7469, 30.0871) -> (22.9182, 29.9998)
  line L1087 (22.9182, 29.9998) -> (23.0737, 29.8868)
  line L1088 (23.0737, 29.8868) -> (23.2096, 29.7509)
  line L1089 (23.2096, 29.7509) -> (23.3226, 29.5954)
  line L1090 (23.3226, 29.5954) -> (23.4099, 29.4241)
  line L1091 (23.4099, 29.4241) -> (23.4693, 29.2413)
  line L1092 (23.4693, 29.2413) -> (23.4993, 29.0514)
  line L1093 (23.4993, 29.0514) -> (23.4993, 28.8592)
  line L1094 (23.4993, 28.8592) -> (23.4693, 28.6693)
  line L1095 (23.4693, 28.6693) -> (23.4099, 28.4865)
  line L1096 (23.4099, 28.4865) -> (23.3226, 28.3153)
  line L1097 (23.3226, 28.3153) -> (23.2096, 28.1597)
  line L1098 (23.2096, 28.1597) -> (23.0737, 28.0238)
  line L1099 (23.0737, 28.0238) -> (22.9182, 27.9108)
  line L1100 (22.9182, 27.9108) -> (22.7469, 27.8236)
  line L1101 (22.7469, 27.8236) -> (22.5641, 27.7642)
  line L1102 (22.5641, 27.7642) -> (22.3742, 27.7341)
  line L1103 (22.3742, 27.7341) -> (22.2781, 27.7303)
  line L1104 (22.2781, 27.7303) -> (21.7281, 27.7303)
  line L1105 (21.7281, 27.7303) -> (21.632, 27.7341)
  line L1106 (21.632, 27.7341) -> (21.4421, 27.7642)
  line L1107 (21.4421, 27.7642) -> (21.2593, 27.8236)
  line L1108 (21.2593, 27.8236) -> (21.0881, 27.9108)
  line L1109 (21.0881, 27.9108) -> (20.9325, 28.0238)
  line L1110 (20.9325, 28.0238) -> (20.7966, 28.1597)
  line L1111 (20.7966, 28.1597) -> (20.6836, 28.3153)
  line L1112 (20.6836, 28.3153) -> (20.5964, 28.4865)
  line L1113 (20.5964, 28.4865) -> (20.537, 28.6693)
  line L1114 (20.537, 28.6693) -> (20.5069, 28.8592)
  line L1115 (20.5069, 28.8592) -> (20.5069, 29.0514)
  line L1116 (20.5069, 29.0514) -> (20.537, 29.2413)
  line L1117 (20.537, 29.2413) -> (20.5964, 29.4241)
  line L1118 (20.5964, 29.4241) -> (20.6836, 29.5954)
  line L1119 (20.6836, 29.5954) -> (20.7966, 29.7509)
  line L1120 (20.7966, 29.7509) -> (20.9325, 29.8868)
  line L1121 (20.9325, 29.8868) -> (21.0881, 29.9998)
  line L1122 (21.0881, 29.9998) -> (21.2593, 30.0871)
  line L1123 (21.2593, 30.0871) -> (21.4421, 30.1465)
  line L1124 (21.4421, 30.1465) -> (21.632, 30.1765)
  line L1125 (21.632, 30.1765) -> (21.7281, 30.1803)
  line L1126 (21.7281, 30.1803) -> (22.2781, 30.1803)
  line L1127 (22.2781, 30.1803) -> (22.3742, 30.1765)
  line L1128 (83.3342, 30.1765) -> (83.5241, 30.1465)
  line L1129 (83.5241, 30.1465) -> (83.7069, 30.0871)
  line L1130 (83.7069, 30.0871) -> (83.8782, 29.9998)
  line L1131 (83.8782, 29.9998) -> (84.0337, 29.8868)
  line L1132 (84.0337, 29.8868) -> (84.1696, 29.7509)
  line L1133 (84.1696, 29.7509) -> (84.2826, 29.5954)
  line L1134 (84.2826, 29.5954) -> (84.3699, 29.4241)
  line L1135 (84.3699, 29.4241) -> (84.4293, 29.2413)
  line L1136 (84.4293, 29.2413) -> (84.4593, 29.0514)
  line L1137 (84.4593, 29.0514) -> (84.4593, 28.8592)
  line L1138 (84.4593, 28.8592) -> (84.4293, 28.6693)
  line L1139 (84.4293, 28.6693) -> (84.3699, 28.4865)
  line L1140 (84.3699, 28.4865) -> (84.2826, 28.3153)
  line L1141 (84.2826, 28.3153) -> (84.1696, 28.1597)
  line L1142 (84.1696, 28.1597) -> (84.0337, 28.0238)
  line L1143 (84.0337, 28.0238) -> (83.8782, 27.9108)
  line L1144 (83.8782, 27.9108) -> (83.7069, 27.8236)
  line L1145 (83.7069, 27.8236) -> (83.5241, 27.7642)
  line L1146 (83.5241, 27.7642) -> (83.3342, 27.7341)
  line L1147 (83.3342, 27.7341) -> (83.2381, 27.7303)
  line L1148 (83.2381, 27.7303) -> (82.6881, 27.7303)
  line L1149 (82.6881, 27.7303) -> (82.592, 27.7341)
  line L1150 (82.592, 27.7341) -> (82.4021, 27.7642)
  line L1151 (82.4021, 27.7642) -> (82.2193, 27.8236)
  line L1152 (82.2193, 27.8236) -> (82.0481, 27.9108)
  line L1153 (82.0481, 27.9108) -> (81.8925, 28.0238)
  line L1154 (81.8925, 28.0238) -> (81.7566, 28.1597)
  line L1155 (81.7566, 28.1597) -> (81.6436, 28.3153)
  line L1156 (81.6436, 28.3153) -> (81.5564, 28.4865)
  line L1157 (81.5564, 28.4865) -> (81.497, 28.6693)
  line L1158 (81.497, 28.6693) -> (81.4669, 28.8592)
  line L1159 (81.4669, 28.8592) -> (81.4669, 29.0514)
  line L1160 (81.4669, 29.0514) -> (81.497, 29.2413)
  line L1161 (81.497, 29.2413) -> (81.5564, 29.4241)
  line L1162 (81.5564, 29.4241) -> (81.6436, 29.5954)
  line L1163 (81.6436, 29.5954) -> (81.7566, 29.7509)
  line L1164 (81.7566, 29.7509) -> (81.8925, 29.8868)
  line L1165 (81.8925, 29.8868) -> (82.0481, 29.9998)
  line L1166 (82.0481, 29.9998) -> (82.2193, 30.0871)
  line L1167 (82.2193, 30.0871) -> (82.4021, 30.1465)
  line L1168 (82.4021, 30.1465) -> (82.592, 30.1765)
  line L1169 (82.592, 30.1765) -> (82.6881, 30.1803)
  line L1170 (82.6881, 30.1803) -> (83.2381, 30.1803)
  line L1171 (83.2381, 30.1803) -> (83.3342, 30.1765)
  line L1172 (12.0488, 27.7942) -> (9.0488, 27.7942)
  line L1173 (9.0488, 27.7942) -> (9.0488, 30.2442)
  line L1174 (9.0488, 30.2442) -> (12.0488, 30.2442)
  line L1175 (12.0488, 30.2442) -> (12.0488, 27.7942)
  line L1176 (73.0088, 27.7942) -> (70.0088, 27.7942)
  line L1177 (70.0088, 27.7942) -> (70.0088, 30.2442)
  line L1178 (70.0088, 30.2442) -> (73.0088, 30.2442)
  line L1179 (73.0088, 30.2442) -> (73.0088, 27.7942)
  line L1180 (43.8465, 29.9037) -> (44.0388, 29.8654)
  line L1181 (44.0388, 29.8654) -> (44.2199, 29.7904)
  line L1182 (44.2199, 29.7904) -> (44.3829, 29.6815)
  line L1183 (44.3829, 29.6815) -> (44.5215, 29.5429)
  line L1184 (44.5215, 29.5429) -> (44.6304, 29.3799)
  line L1185 (44.6304, 29.3799) -> (44.7054, 29.1988)
  line L1186 (44.7054, 29.1988) -> (44.7437, 29.0065)
  line L1187 (44.7437, 29.0065) -> (44.7437, 28.8105)
  line L1188 (44.7437, 28.8105) -> (44.7054, 28.6182)
  line L1189 (44.7054, 28.6182) -> (44.6304, 28.4371)
  line L1190 (44.6304, 28.4371) -> (44.5215, 28.2741)
  line L1191 (44.5215, 28.2741) -> (44.3829, 28.1355)
  line L1192 (44.3829, 28.1355) -> (44.2199, 28.0266)
  line L1193 (44.2199, 28.0266) -> (44.0388, 27.9515)
  line L1194 (44.0388, 27.9515) -> (43.8465, 27.9133)
  line L1195 (43.8465, 27.9133) -> (43.7485, 27.9085)
  line L1196 (43.7485, 27.9085) -> (42.5485, 27.9085)
  line L1197 (42.5485, 27.9085) -> (42.4505, 27.9133)
  line L1198 (42.4505, 27.9133) -> (42.2582, 27.9515)
  line L1199 (42.2582, 27.9515) -> (42.0771, 28.0266)
  line L1200 (42.0771, 28.0266) -> (41.9141, 28.1355)
  line L1201 (41.9141, 28.1355) -> (41.7755, 28.2741)
  line L1202 (41.7755, 28.2741) -> (41.6666, 28.4371)
  line L1203 (41.6666, 28.4371) -> (41.5915, 28.6182)
  line L1204 (41.5915, 28.6182) -> (41.5533, 28.8105)
  line L1205 (41.5533, 28.8105) -> (41.5533, 29.0065)
  line L1206 (41.5533, 29.0065) -> (41.5915, 29.1988)
  line L1207 (41.5915, 29.1988) -> (41.6666, 29.3799)
  line L1208 (41.6666, 29.3799) -> (41.7755, 29.5429)
  line L1209 (41.7755, 29.5429) -> (41.9141, 29.6815)
  line L1210 (41.9141, 29.6815) -> (42.0771, 29.7904)
  line L1211 (42.0771, 29.7904) -> (42.2582, 29.8654)
  line L1212 (42.2582, 29.8654) -> (42.4505, 29.9037)
  line L1213 (42.4505, 29.9037) -> (42.5485, 29.9085)
  line L1214 (42.5485, 29.9085) -> (43.7485, 29.9085)
  line L1215 (43.7485, 29.9085) -> (43.8465, 29.9037)
  line L1216 (104.8065, 29.9037) -> (104.9988, 29.8654)
  line L1217 (104.9988, 29.8654) -> (105.1799, 29.7904)
  line L1218 (105.1799, 29.7904) -> (105.3429, 29.6815)
  line L1219 (105.3429, 29.6815) -> (105.4815, 29.5429)
  line L1220 (105.4815, 29.5429) -> (105.5904, 29.3799)
  line L1221 (105.5904, 29.3799) -> (105.6654, 29.1988)
  line L1222 (105.6654, 29.1988) -> (105.7037, 29.0065)
  line L1223 (105.7037, 29.0065) -> (105.7037, 28.8105)
  line L1224 (105.7037, 28.8105) -> (105.6654, 28.6182)
  line L1225 (105.6654, 28.6182) -> (105.5904, 28.4371)
  line L1226 (105.5904, 28.4371) -> (105.4815, 28.2741)
  line L1227 (105.4815, 28.2741) -> (105.3429, 28.1355)
  line L1228 (105.3429, 28.1355) -> (105.1799, 28.0266)
  line L1229 (105.1799, 28.0266) -> (104.9988, 27.9515)
  line L1230 (104.9988, 27.9515) -> (104.8065, 27.9133)
  line L1231 (104.8065, 27.9133) -> (104.7085, 27.9085)
  line L1232 (104.7085, 27.9085) -> (103.5085, 27.9085)
  line L1233 (103.5085, 27.9085) -> (103.4105, 27.9133)
  line L1234 (103.4105, 27.9133) -> (103.2182, 27.9515)
  line L1235 (103.2182, 27.9515) -> (103.0371, 28.0266)
  line L1236 (103.0371, 28.0266) -> (102.8741, 28.1355)
  line L1237 (102.8741, 28.1355) -> (102.7355, 28.2741)
  line L1238 (102.7355, 28.2741) -> (102.6266, 28.4371)
  line L1239 (102.6266, 28.4371) -> (102.5515, 28.6182)
  line L1240 (102.5515, 28.6182) -> (102.5133, 28.8105)
  line L1241 (102.5133, 28.8105) -> (102.5133, 29.0065)
  line L1242 (102.5133, 29.0065) -> (102.5515, 29.1988)
  line L1243 (102.5515, 29.1988) -> (102.6266, 29.3799)
  line L1244 (102.6266, 29.3799) -> (102.7355, 29.5429)
  line L1245 (102.7355, 29.5429) -> (102.8741, 29.6815)
  line L1246 (102.8741, 29.6815) -> (103.0371, 29.7904)
  line L1247 (103.0371, 29.7904) -> (103.2182, 29.8654)
  line L1248 (103.2182, 29.8654) -> (103.4105, 29.9037)
  line L1249 (103.4105, 29.9037) -> (103.5085, 29.9085)
  line L1250 (103.5085, 29.9085) -> (104.7085, 29.9085)
  line L1251 (104.7085, 29.9085) -> (104.8065, 29.9037)
  line L1252 (50.1338, 32.4063) -> (50.3204, 32.3457)
  line L1253 (50.3204, 32.3457) -> (50.4952, 32.2566)
  line L1254 (50.4952, 32.2566) -> (50.6538, 32.1413)
  line L1255 (50.6538, 32.1413) -> (50.7925, 32.0026)
  line L1256 (50.7925, 32.0026) -> (50.9078, 31.8439)